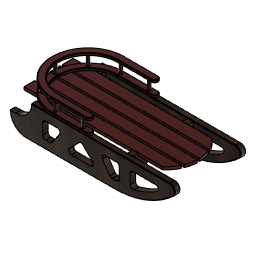
L9_Dobrescu_Diana (Autodesk Fusion 360 design; units mm, degrees)
Autodesk Fusion 360 part; units mm, degrees
ref_plane "WorkPlane1" through (0, 300, 0) normal (0, 1, 0) x (0, 0, 1)
sketch "Sketch1" plane through (0, 300, 0) normal (0, 1, 0) x (1, 0, 0)
  line L0 (0, 0) -> (-450, 0)
  line L1 (0, 0) -> (0, 300) construction
  line L2 (0, 300) -> (-500, 300)
  line L3 (-500, 300) -> (-500, 150) construction
  line L4 (-600, 150) -> (-650, 150)
  line L5 (-450, 0) -> (-600, 0) construction
  arc A0 (-450, 0) -> (-600, 150) centre (-600, 0) ccw
  arc A1 (-500, 300) -> (-649.7593, 141.5062) centre (-500, 150) ccw
  line L6 (-500, 300) -> (300, 300)
  line L7 (300, 300) -> (300, -500) construction
  line L8 (0, 0) -> (924.4998, 0)
  arc A2 (924.4998, 0) -> (300, 300) centre (300, -500) ccw
  dimension "d2" = 450
  dimension "d3" = 300
  dimension "d4" = 500
  dimension "d5" = 150
  dimension "d8" = 800
  dimension "d27" = 800
  dimension "d116" = 150
  constraint coincident L0.start L1.start
  constraint horizontal L0
  constraint vertical L1
  constraint perpendicular L1 L2
  constraint perpendicular L2 L3
  constraint coincident L3.end A1.centre
  constraint coincident L4.end A1
  constraint perpendicular L3 L4
  constraint parallel L0 L5
  constraint coincident L5.end A0.centre
  constraint tangent L4 A0
  constraint perpendicular L1 L6
  constraint perpendicular L6 L7
  constraint coincident L7.end A2.centre
  constraint perpendicular L1 L8
  measures "d2" distance of L0.start L0.end
  measures "d3" distance of L0.start L1.end
  measures "d4" distance of L1.end L2.end
  measures "d5" distance of L2.end L3.end
  measures "d8" distance of L2.end L6.end
  measures "d27" radius of A2
  measures "d116" radius of A0
extrude "Extrude1" add sketch "Sketch1" along normal mid plane 50 makes body 1
fillet "Fillet1" radius 50 1 edges at (924.4998, 300, 0) on bodies 1
mirror "Mirror1" about plane through (0, 0, 0) normal (0, 1, 0) of bodies 1 makes body 2
fillet "Fillet3" radius 5 20 edges at (-606.066, 275, -256.066) (-100, 275, -300) (592.1187, 275, -244.7595) (856.4494, 275, -31.7426) (179.951, 275, 0) (179.951, 325, 0) (856.4494, 325, -31.7426) (592.1187, 325, -244.7595) (-100, 325, -300) (-606.066, 325, -256.066) (179.951, -325, 0) (856.4494, -325, -31.7426) (592.1187, -325, -244.7595) (-100, -325, -300) (-606.066, -325, -256.066) (-606.066, -275, -256.066) (-100, -275, -300) (592.1187, -275, -244.7595) (856.4494, -275, -31.7426) (179.951, -275, 0) on bodies 1 2
ref_plane "WorkPlane4" through (-425, 0, 0) normal (1, 0, 0) x (0, 1, 0)
sketch "Sketch4" plane through (-425, 0, 0) normal (1, 0, 0) x (0, 1, 0)
  line L0 (275, -5) -> (275, -155)
  line L1 (275, -5) -> (225, -5)
  line L2 (225, -5) -> (225, -25)
  line L3 (225, -25) -> (0, -25)
  line L4 (275, -155) -> (198.4313, -155)
  line L5 (0, -25) -> (0, -80) construction
  line L6 (-225, -25) -> (0, -25)
  line L7 (-275, -5) -> (-225, -5)
  line L8 (-225, -5) -> (-225, -25)
  line L9 (-275, -5) -> (-275, -155)
  line L10 (-275, -155) -> (-198.4313, -155)
  arc A0 (198.4313, -155) -> (-198.4313, -155) centre (0, -380) ccw
  dimension "d41" = 150
  dimension "d43" = 50
  dimension "d44" = 20
  dimension "d47" = 300
  constraint vertical L0
  constraint perpendicular L0 L1
  constraint perpendicular L1 L2
  constraint perpendicular L2 L3
  constraint perpendicular L0 L4
  constraint coincident L5.end A0
  constraint perpendicular L3 L5
  constraint symmetric L0.start L5 L7.start
  constraint symmetric L0.end L5 L9.end
  constraint symmetric L1.end L5 L7.end
  constraint symmetric L2.end L5 L6.start
  constraint symmetric L3.end L5 L6.end
  constraint symmetric L4.end L5 L10.end
  measures "d41" distance of L0.start L0.end
  measures "d43" distance of L0.start L1.end
  measures "d44" distance of L1.end L2.end
  measures "d47" radius of A0
extrude "Extrude3" add sketch "Sketch4" along normal blind 50 separate body makes body 3
mirror "Mirror2" about plane through (0, 0, 0) normal (1, 0, 0) of bodies 3 makes body 4
sketch "Sketch5" plane through (0, 0, 0) normal (0, 0, 1) x (1, 0, 0)
  line L0 (0, 0) -> (0, 417.1711) construction
  line L1 (0, 273.7228) -> (0, 223.7228)
  line L2 (0, 223.7228) -> (-620, 223.7228)
  line L3 (-620, 223.7228) -> (-620, 126.2228)
  line L4 (-620, 126.2228) -> (760, 126.2228)
  line L5 (760, 126.2228) -> (760, 223.7228)
  line L6 (760, 223.7228) -> (0, 223.7228)
  line L7 (-620, 8.7228) -> (760, 8.7228)
  line L8 (0, 106.2228) -> (-620, 106.2228)
  line L9 (760, 106.2228) -> (0, 106.2228)
  line L10 (760, 8.7228) -> (760, 106.2228)
  line L11 (-620, 106.2228) -> (-620, 8.7228)
  line L12 (-620, -108.7772) -> (760, -108.7772)
  line L13 (0, -11.2772) -> (-620, -11.2772)
  line L14 (760, -11.2772) -> (0, -11.2772)
  line L15 (760, -108.7772) -> (760, -11.2772)
  line L16 (-620, -11.2772) -> (-620, -108.7772)
  line L17 (-620, -226.2772) -> (760, -226.2772)
  line L18 (0, -128.7772) -> (-620, -128.7772)
  line L19 (760, -128.7772) -> (0, -128.7772)
  line L20 (760, -226.2772) -> (760, -128.7772)
  line L21 (-620, -128.7772) -> (-620, -226.2772)
  dimension "d52" = 50
  dimension "d53" = 620
  dimension "d54" = 97.5
  dimension "d55" = 1380
  dimension "d58" = 117.5
  dimension "d59" = -117.5
  constraint coincident L0.start origin
  constraint vertical L0
  constraint coincident L0 L1.start
  constraint vertical L1
  constraint perpendicular L1 L2
  constraint perpendicular L2 L3
  constraint perpendicular L0 L4
  constraint perpendicular L2 L5
  constraint perpendicular L0 L6
  measures "d52" distance of L1.start L1.end
  measures "d53" distance of L1.end L2.end
  measures "d54" distance of L2.end L3.end
  measures "d55" distance of L3.end L4.end
extrude "Extrude4" add sketch "Sketch5" against normal blind 25 separate body makes body 5 at (-160, -43.7772, 0) makes body 6 at (-160, 73.7228, 0) makes body 7 at (-160, -161.2772, 0) makes body 8 at (300, 158.7228, 0)
sketch "Sketch6" plane through (0, 0, 0) normal (0, 0, 1) x (1, 0, 0)
  line L0 (0, 0) -> (450, 0) construction
  arc A0 (450, -300) -> (450, 300) centre (450, 0) ccw
  line L1 (450, 300) -> (759.9274, 300)
  line L2 (759.9991, -300) -> (450, -300)
  line L3 (784.9848, 0.2651) -> (784.9848, 300)
  line L4 (784.9848, 300) -> (759.9274, 300)
  line L5 (784.9848, 0.2651) -> (784.9848, -300)
  line L6 (784.9848, -300) -> (759.9991, -300)
  dimension "d62" = 450
  dimension "d63" = 300
  constraint coincident L0.start origin
  constraint horizontal L0
  constraint coincident L0.end A0.centre
  constraint tangent A0 L2
  constraint tangent A0 L1
  constraint perpendicular L1 L3
  constraint horizontal L4
  constraint perpendicular L2 L5
  constraint perpendicular L3 L4
  constraint perpendicular L5 L6
  constraint horizontal L2
  measures "d62" distance of L0.start L0.end
  measures "d63" radius of A0
extrude "Extrude5" cut sketch "Sketch6" against normal blind 25 bodies 5 6 7 8
sketch "Sketch7" plane through (0, 0, 0) normal (0, 0, 1) x (1, 0, 0)
  line L0 (0, 0) -> (-260, 0)
  line L1 (50, 270) -> (-260, 270)
  line L2 (50, 330) -> (-260, 330)
  line L3 (50, -270) -> (-260, -270)
  line L4 (50, -330) -> (-260, -330)
  arc A0 (-260, 330) -> (-260, -330) centre (-260, 0) ccw
  arc A1 (-260, 270) -> (-260, -270) centre (-260, 0) ccw
  arc A2 (50, -330) -> (50, -270) centre (50, -300) ccw
  arc A3 (50, 270) -> (50, 330) centre (50, 300) ccw
  dimension "d69" = 260
  dimension "d71" = 60
  dimension "d74" = 60
  dimension "d75" = 270
  constraint coincident L0.start origin
  constraint horizontal L0
  constraint coincident L0.end A0.centre
  constraint tangent L1 A1
  constraint horizontal L1
  constraint concentric A0 A1
  constraint tangent L2 A3
  constraint horizontal L2
  constraint tangent L2 A0
  constraint symmetric L0 A2 A3
  constraint symmetric L0 L1.start L3.start
  constraint symmetric L0 L1.end L3.end
  constraint symmetric L0 L2.start L4.start
  constraint symmetric L0 L2.end L4.end
  measures "d69" distance of L0.start L0.end
  measures "d71" diameter of A3
  measures "d74" distance of A0 A1
  measures "d75" radius of A1
extrude "Extrude6" add sketch "Sketch7" along normal blind 25 separate body makes body 9
fillet "Fillet4" radius 5 16 edges at (80, -300, 25) (-105, -270, 25) (-530, 0, 25) (-105, 270, 25) (80, 300, 25) (-105, 330, 25) (-590, 0, 25) (-105, -330, 25) (-105, -330, 0) (80, -300, 0) (-105, -270, 0) (-530, 0, 0) (-105, 270, 0) (80, 300, 0) (-105, 330, 0) (-590, 0, 0) on bodies 9
sketch "Sketch8" plane through (0, 0, 25) normal (0, 0, 1) x (-1, 0, 0)
  arc A0 (-50, 325) -> (-50, 275) centre (-50, 300) ccw
  line L0 (-50, 275) -> (260, 275)
  arc A1 (260, -275) -> (260, 275) centre (260, 0) ccw
  line L1 (260, -275) -> (-50, -275)
  arc A2 (-50, -275) -> (-50, -325) centre (-50, -300) ccw
  line L2 (-50, -325) -> (260, -325)
  arc A3 (260, -325) -> (260, 325) centre (260, 0) ccw
  line L3 (260, 325) -> (-50, 325)
  line L4 (0, 0) -> (0, 300) construction
  circle A4 centre (0, 300) radius 15
  line L5 (0, 0) -> (0, -300) construction
  circle A5 centre (0, -300) radius 15
  line L6 (0, 300) -> (260, 300) construction
  circle A6 centre (260, 300) radius 15
  circle A7 centre (472.132, 212.132) radius 15
  circle A8 centre (560, 0) radius 15
  circle A9 centre (472.132, -212.132) radius 15
  circle A10 centre (260, -300) radius 15
  dimension "d80" = 30
  dimension "d81" = 30
  dimension "d82" = 260
  dimension "d83" = 30
  dimension "d85" = -180
  constraint coincident L4.start L5.start
  constraint perpendicular L3 L4
  constraint coincident L4.end A4.centre
  constraint perpendicular L1 L5
  constraint coincident L5.end A5.centre
  constraint parallel L0 L6
  constraint coincident L6.end A6.centre
  measures "d80" diameter of A4
  measures "d81" diameter of A5
  measures "d82" distance of L4.end L6.end
  measures "d83" diameter of A6
extrude "Extrude7" add sketch "Sketch8" along normal blind 105 separate body contours A4 | A5 | A6 | A7 | A8 | A9 | A10 makes body 10 at (-14.5362, -303.7014, 95) makes body 11 at (-487.0575, 213.6256, 95) makes body 12 at (-245.4638, -303.7014, 95) makes body 13 at (-14.5362, 296.2986, 95) makes body 14 at (-553.8307, -13.6726, 95) makes body 15 at (-487.0575, -210.6385, 95) makes body 16 at (-274.5362, 296.2986, 95)
pattern_linear "R-Pattern1" count 2 spacing 120 along (0, 0, 1) of bodies 9 makes body 17
sketch "Sketch10" plane through (0, 0, 0) normal (0, 1, 0) x (1, 0, 0)
  line L0 (150, 225) -> (0, 75)
  line L1 (0, 225) -> (270, 225) construction
  line L2 (350, 75) -> (170, 75)
  arc A0 (450, 225) -> (760, 75) centre (291.5323, -497.8333) cw
  line L3 (0, 300) -> (0, 225) construction
  line L4 (0, 0) -> (0, 75) construction
  line L5 (270, 225) -> (350, 225)
  line L6 (450, 75) -> (450, 225)
  line L7 (450, 75) -> (760, 75)
  line L8 (0, 0) -> (0, 300) construction
  line L9 (170, 75) -> (270, 225)
  line L10 (350, 225) -> (350, 75)
  line L11 (0, 225) -> (150, 225)
  line L12 (-150, 225) -> (0, 75)
  line L13 (-170, 75) -> (-270, 225)
  line L14 (-350, 75) -> (-170, 75)
  line L15 (-350, 225) -> (-350, 75)
  line L16 (-270, 225) -> (-350, 225)
  line L17 (0, 225) -> (-150, 225)
  point P0 (-700, 150)
  point P1 (-500, 150)
  dimension "d104" = 80
  dimension "d107" = 310
  dimension "d108" = 740
  dimension "d110" = 180
  dimension "d111" = 300
  dimension "d112" = 75
  dimension "d113" = 75
  dimension "d114" = 760
  dimension "d115" = 350
  constraint parallel L2 L5
  constraint horizontal L7
  constraint vertical L6
  constraint horizontal L2
  constraint vertical L10
  constraint symmetric L5.end L8 L15.start
  constraint symmetric L1.end L8 L13.end
  constraint symmetric L0.end L8 L4.end
  constraint symmetric L2.start L8 L14.start
  constraint symmetric L1.start L8 L3.end
  constraint symmetric L0.start L8 L12.start
  constraint symmetric L2.end L8 L13.start
  measures "d104" distance of L5.end L1.end
  measures "d107" distance of L6.start A0.end
  measures "d108" radius of A0
  measures "d110" distance of L2.start L2.end
  measures "d111" distance of L0.start L12.start
  measures "d112" distance of L3.start L17
  measures "d113" distance of L0.end L4.start
  measures "d114" distance of L0.end A0.end
  measures "d115" distance of L5.end L1.start
extrude "Extrude8" cut sketch "Sketch10" along normal mid plane 650 bodies 1 2
fillet "Fillet5" radius 25 28 edges at (-270, 300, -225) (-170, 300, -75) (-350, 300, -75) (-350, 300, -225) (-150, 300, -225) (0, 300, -75) (150, 300, -225) (170, 300, -75) (350, 300, -75) (350, 300, -225) (270, 300, -225) (450, 300, -75) (450, 300, -225) (760, 300, -75) (760, -300, -75) (450, -300, -225) (450, -300, -75) (350, -300, -75) (170, -300, -75) (270, -300, -225) (350, -300, -225) (0, -300, -75) (150, -300, -225) (-150, -300, -225) (-170, -300, -75) (-350, -300, -75) (-350, -300, -225) (-270, -300, -225) on bodies 1 2
